cdx-3r-gripper-2-sliding (Autodesk Fusion 360 design; units mm, degrees)
part number: 2026-10-18-13-23-23-866
part number: 2026-10-18-13-23-24-152
part number: 2026-10-18-22-47-35-715
part number: 2026-10-18-22-47-35-720
part number: 2026-10-18-22-47-40-472
part number: 2026-10-18-22-47-42-045
part number: 2026-10-18-22-48-08-572
part number: 2026-10-18-22-48-13-413
part number: 2026-10-19-20-53-59-264
part number: 2026-10-19-20-54-15-154
part number: 2026-10-19-20-58-47-392
part number: 2026-10-19-20-59-14-619
part number: 2026-10-19-21-25-58-125
part number: 2026-10-19-21-26-03-440
part number: 2026-10-19-21-30-46-172
part number: 2026-10-19-21-31-41-430
part number: 2026-10-19-21-31-41-551
part number: 2026-10-19-21-31-56-859
part number: 2026-10-19-21-32-19-291
part number: 2026-10-19-21-32-20-248
part number: 2026-10-19-21-32-33-847
part number: 2026-10-19-21-32-36-535
part number: 2026-10-19-21-32-39-259
part number: 2026-10-19-21-32-56-072
Autodesk Fusion 360 part; units mm, degrees
(part 1 of 5)
ref_plane "WorkPlane1" through (-175, 0, 0) normal (1, 0, 0) x (0, 1, 0) in component "Gripper rail base (printed)"
sketch "spine" plane through (-175, 0, 0) normal (1, 0, 0) x (0, 0, -1) in component "Gripper rail base (printed)"
  line L0 (12, 15) -> (12, 20)
  line L1 (12, 20) -> (-12, 20)
  line L2 (-12, 20) -> (-12, 15)
  line L3 (-12, 15) -> (-12, 15)
  line L4 (-12, 15) -> (-12, 6)
  line L5 (-12, 6) -> (12, 6)
  line L6 (12, 6) -> (12, 15)
  line L7 (12, 15) -> (12, 15)
extrude "spine (1)" add sketch "spine" along normal blind 175.31 makes body 1 in component "Gripper rail base (printed)"
ref_plane "WorkPlane2" through (-130, 0, 0) normal (1, 0, 0) x (0, 1, 0) in component "Gripper rail base (printed)"
sketch "pipe clip" plane through (-130, 0, 0) normal (1, 0, 0) x (0, 0, -1) in component "Gripper rail base (printed)"
  circle A0 centre (0, 0) radius 14.5
  circle A1 centre (0, 0) radius 10.95
extrude "pipe clip (1)" add sketch "pipe clip" along normal blind 12 separate body makes body 2 in component "Gripper rail base (printed)"
ref_plane "WorkPlane3" through (-50, 0, 0) normal (1, 0, 0) x (0, 1, 0) in component "Gripper rail base (printed)"
sketch "pipe clip (1)" plane through (-50, 0, 0) normal (1, 0, 0) x (0, 0, -1) in component "Gripper rail base (printed)"
  circle A0 centre (0, 0) radius 14.5
  circle A1 centre (0, 0) radius 10.95
extrude "pipe clip (2)" add sketch "pipe clip (1)" along normal blind 12 separate body makes body 3 in component "Gripper rail base (printed)"
ref_plane "WorkPlane4" through (0, 0, -12) normal (0, 0, 1) x (1, 0, 0) in component "Gripper rail base (printed)"
sketch "front tab" plane through (0, 0, -12) normal (0, 0, 1) x (1, 0, 0) in component "Gripper rail base (printed)"
  line L0 (0.3, 6) -> (8.3, 6)
  line L1 (8.3, 6) -> (8.3, 20)
  line L2 (8.3, 20) -> (0.3, 20)
  line L3 (0.3, 20) -> (0.3, 6)
extrude "front tab (1)" add sketch "front tab" along normal blind 24 separate body makes body 4 in component "Gripper rail base (printed)"
ref_plane "WorkPlane5" through (0, 16.5, 0) normal (0, 1, 0) x (0, 0, 1) in component "Gripper rail base (printed)"
sketch "rack" plane through (0, 16.5, 0) normal (0, 1, 0) x (1, 0, 0) in component "Gripper rail base (printed)"
  line L0 (-150, -11.5) -> (-150, -12)
  line L1 (-150, -12) -> (-149.6696, -12)
  line L2 (-149.6696, -12) -> (-148.8506, -14.25)
  line L3 (-148.8506, -14.25) -> (-148.0078, -14.25)
  line L4 (-148.0078, -14.25) -> (-147.1888, -12)
  line L5 (-147.1888, -12) -> (-146.528, -12)
  line L6 (-146.528, -12) -> (-145.709, -14.25)
  line L7 (-145.709, -14.25) -> (-144.8662, -14.25)
  line L8 (-144.8662, -14.25) -> (-144.0473, -12)
  line L9 (-144.0473, -12) -> (-143.3864, -12)
  line L10 (-143.3864, -12) -> (-142.5674, -14.25)
  line L11 (-142.5674, -14.25) -> (-141.7246, -14.25)
  line L12 (-141.7246, -14.25) -> (-140.9057, -12)
  line L13 (-140.9057, -12) -> (-140.2448, -12)
  line L14 (-140.2448, -12) -> (-139.4259, -14.25)
  line L15 (-139.4259, -14.25) -> (-138.583, -14.25)
  line L16 (-138.583, -14.25) -> (-137.7641, -12)
  line L17 (-137.7641, -12) -> (-137.1032, -12)
  line L18 (-137.1032, -12) -> (-136.2843, -14.25)
  line L19 (-136.2843, -14.25) -> (-135.4414, -14.25)
  line L20 (-135.4414, -14.25) -> (-134.6225, -12)
  line L21 (-134.6225, -12) -> (-133.9616, -12)
  line L22 (-133.9616, -12) -> (-133.1427, -14.25)
  line L23 (-133.1427, -14.25) -> (-132.2998, -14.25)
  line L24 (-132.2998, -14.25) -> (-131.4809, -12)
  line L25 (-131.4809, -12) -> (-130.82, -12)
  line L26 (-130.82, -12) -> (-130.0011, -14.25)
  line L27 (-130.0011, -14.25) -> (-129.1582, -14.25)
  line L28 (-129.1582, -14.25) -> (-128.3393, -12)
  line L29 (-128.3393, -12) -> (-127.6784, -12)
  line L30 (-127.6784, -12) -> (-126.8595, -14.25)
  line L31 (-126.8595, -14.25) -> (-126.0166, -14.25)
  line L32 (-126.0166, -14.25) -> (-125.1977, -12)
  line L33 (-125.1977, -12) -> (-124.5368, -12)
  line L34 (-124.5368, -12) -> (-123.7179, -14.25)
  line L35 (-123.7179, -14.25) -> (-122.875, -14.25)
  line L36 (-122.875, -14.25) -> (-122.0561, -12)
  line L37 (-122.0561, -12) -> (-121.3952, -12)
  line L38 (-121.3952, -12) -> (-120.5763, -14.25)
  line L39 (-120.5763, -14.25) -> (-119.7334, -14.25)
  line L40 (-119.7334, -14.25) -> (-118.9145, -12)
  line L41 (-118.9145, -12) -> (-118.2536, -12)
  line L42 (-118.2536, -12) -> (-117.4347, -14.25)
  line L43 (-117.4347, -14.25) -> (-116.5918, -14.25)
  line L44 (-116.5918, -14.25) -> (-115.7729, -12)
  line L45 (-115.7729, -12) -> (-115.112, -12)
  line L46 (-115.112, -12) -> (-114.2931, -14.25)
  line L47 (-114.2931, -14.25) -> (-113.4503, -14.25)
  line L48 (-113.4503, -14.25) -> (-112.6313, -12)
  line L49 (-112.6313, -12) -> (-111.9705, -12)
  line L50 (-111.9705, -12) -> (-111.1515, -14.25)
  line L51 (-111.1515, -14.25) -> (-110.3087, -14.25)
  line L52 (-110.3087, -14.25) -> (-109.4897, -12)
  line L53 (-109.4897, -12) -> (-108.8289, -12)
  line L54 (-108.8289, -12) -> (-108.0099, -14.25)
  line L55 (-108.0099, -14.25) -> (-107.1671, -14.25)
  line L56 (-107.1671, -14.25) -> (-106.3481, -12)
  line L57 (-106.3481, -12) -> (-105.6873, -12)
  line L58 (-105.6873, -12) -> (-104.8683, -14.25)
  line L59 (-104.8683, -14.25) -> (-104.0255, -14.25)
  line L60 (-104.0255, -14.25) -> (-103.2065, -12)
  line L61 (-103.2065, -12) -> (-102.5457, -12)
  line L62 (-102.5457, -12) -> (-101.7267, -14.25)
  line L63 (-101.7267, -14.25) -> (-100.8839, -14.25)
  line L64 (-100.8839, -14.25) -> (-100.065, -12)
  line L65 (-100.065, -12) -> (-99.4041, -12)
  line L66 (-99.4041, -12) -> (-98.5851, -14.25)
  line L67 (-98.5851, -14.25) -> (-97.7423, -14.25)
  line L68 (-97.7423, -14.25) -> (-96.9234, -12)
  line L69 (-96.9234, -12) -> (-96.2625, -12)
  line L70 (-96.2625, -12) -> (-95.4436, -14.25)
  line L71 (-95.4436, -14.25) -> (-94.6007, -14.25)
  line L72 (-94.6007, -14.25) -> (-93.7818, -12)
  line L73 (-93.7818, -12) -> (-93.1209, -12)
  line L74 (-93.1209, -12) -> (-92.302, -14.25)
  line L75 (-92.302, -14.25) -> (-91.4591, -14.25)
  line L76 (-91.4591, -14.25) -> (-90.6402, -12)
  line L77 (-90.6402, -12) -> (-89.9793, -12)
  line L78 (-89.9793, -12) -> (-89.1604, -14.25)
  line L79 (-89.1604, -14.25) -> (-88.3175, -14.25)
  line L80 (-88.3175, -14.25) -> (-87.4986, -12)
  line L81 (-87.4986, -12) -> (-86.8377, -12)
  line L82 (-86.8377, -12) -> (-86.0188, -14.25)
  line L83 (-86.0188, -14.25) -> (-85.1759, -14.25)
  line L84 (-85.1759, -14.25) -> (-84.357, -12)
  line L85 (-84.357, -12) -> (-83.6961, -12)
  line L86 (-83.6961, -12) -> (-82.8772, -14.25)
  line L87 (-82.8772, -14.25) -> (-82.0343, -14.25)
  line L88 (-82.0343, -14.25) -> (-81.2154, -12)
  line L89 (-81.2154, -12) -> (-80.5545, -12)
  line L90 (-80.5545, -12) -> (-79.7356, -14.25)
  line L91 (-79.7356, -14.25) -> (-78.8927, -14.25)
  line L92 (-78.8927, -14.25) -> (-78.0738, -12)
  line L93 (-78.0738, -12) -> (-77.4129, -12)
  line L94 (-77.4129, -12) -> (-76.594, -14.25)
  line L95 (-76.594, -14.25) -> (-75.7511, -14.25)
  line L96 (-75.7511, -14.25) -> (-74.9322, -12)
  line L97 (-74.9322, -12) -> (-74.2713, -12)
  line L98 (-74.2713, -12) -> (-73.4524, -14.25)
  line L99 (-73.4524, -14.25) -> (-72.6096, -14.25)
  line L100 (-72.6096, -14.25) -> (-71.7906, -12)
  line L101 (-71.7906, -12) -> (-71.1297, -12)
  line L102 (-71.1297, -12) -> (-70.3108, -14.25)
  line L103 (-70.3108, -14.25) -> (-69.468, -14.25)
  line L104 (-69.468, -14.25) -> (-68.649, -12)
  line L105 (-68.649, -12) -> (-67.9882, -12)
  line L106 (-67.9882, -12) -> (-67.1692, -14.25)
  line L107 (-67.1692, -14.25) -> (-66.3264, -14.25)
  line L108 (-66.3264, -14.25) -> (-65.5074, -12)
  line L109 (-65.5074, -12) -> (-64.8466, -12)
  line L110 (-64.8466, -12) -> (-64.0276, -14.25)
  line L111 (-64.0276, -14.25) -> (-63.1848, -14.25)
  line L112 (-63.1848, -14.25) -> (-62.3658, -12)
  line L113 (-62.3658, -12) -> (-61.705, -12)
  line L114 (-61.705, -12) -> (-60.886, -14.25)
  line L115 (-60.886, -14.25) -> (-60.0432, -14.25)
  line L116 (-60.0432, -14.25) -> (-59.2242, -12)
  line L117 (-59.2242, -12) -> (-58.5634, -12)
  line L118 (-58.5634, -12) -> (-57.7444, -14.25)
  line L119 (-57.7444, -14.25) -> (-56.9016, -14.25)
  line L120 (-56.9016, -14.25) -> (-56.0827, -12)
  line L121 (-56.0827, -12) -> (-55.4218, -12)
  line L122 (-55.4218, -12) -> (-54.6029, -14.25)
  line L123 (-54.6029, -14.25) -> (-53.76, -14.25)
  line L124 (-53.76, -14.25) -> (-52.9411, -12)
  line L125 (-52.9411, -12) -> (-52.2802, -12)
  line L126 (-52.2802, -12) -> (-51.4613, -14.25)
  line L127 (-51.4613, -14.25) -> (-50.6184, -14.25)
  line L128 (-50.6184, -14.25) -> (-49.7995, -12)
  line L129 (-49.7995, -12) -> (-49.1386, -12)
  line L130 (-49.1386, -12) -> (-48.3197, -14.25)
  line L131 (-48.3197, -14.25) -> (-47.4768, -14.25)
  line L132 (-47.4768, -14.25) -> (-46.6579, -12)
  line L133 (-46.6579, -12) -> (-45.997, -12)
  line L134 (-45.997, -12) -> (-45.1781, -14.25)
  line L135 (-45.1781, -14.25) -> (-44.3352, -14.25)
  line L136 (-44.3352, -14.25) -> (-43.5163, -12)
  line L137 (-43.5163, -12) -> (-42.8554, -12)
  line L138 (-42.8554, -12) -> (-42.0365, -14.25)
  line L139 (-42.0365, -14.25) -> (-41.1936, -14.25)
  line L140 (-41.1936, -14.25) -> (-40.3747, -12)
  line L141 (-40.3747, -12) -> (-39.7138, -12)
  line L142 (-39.7138, -12) -> (-38.8949, -14.25)
  line L143 (-38.8949, -14.25) -> (-38.052, -14.25)
  line L144 (-38.052, -14.25) -> (-37.2331, -12)
  line L145 (-37.2331, -12) -> (-36.5722, -12)
  line L146 (-36.5722, -12) -> (-35.7533, -14.25)
  line L147 (-35.7533, -14.25) -> (-34.9104, -14.25)
  line L148 (-34.9104, -14.25) -> (-34.0915, -12)
  line L149 (-34.0915, -12) -> (-33.4306, -12)
  line L150 (-33.4306, -12) -> (-32.6117, -14.25)
  line L151 (-32.6117, -14.25) -> (-31.7688, -14.25)
  line L152 (-31.7688, -14.25) -> (-30.9499, -12)
  line L153 (-30.9499, -12) -> (-30.289, -12)
  line L154 (-30.289, -12) -> (-29.4701, -14.25)
  line L155 (-29.4701, -14.25) -> (-28.6273, -14.25)
  line L156 (-28.6273, -14.25) -> (-27.8083, -12)
  line L157 (-27.8083, -12) -> (-27.1475, -12)
  line L158 (-27.1475, -12) -> (-26.3285, -14.25)
  line L159 (-26.3285, -14.25) -> (-25.4857, -14.25)
  line L160 (-25.4857, -14.25) -> (-24.6667, -12)
  line L161 (-24.6667, -12) -> (-24.0059, -12)
  line L162 (-24.0059, -12) -> (-23.1869, -14.25)
  line L163 (-23.1869, -14.25) -> (-22.3441, -14.25)
  line L164 (-22.3441, -14.25) -> (-21.5251, -12)
  line L165 (-21.5251, -12) -> (-20.8643, -12)
  line L166 (-20.8643, -12) -> (-20.0453, -14.25)
  line L167 (-20.0453, -14.25) -> (-19.2025, -14.25)
  line L168 (-19.2025, -14.25) -> (-18.3835, -12)
  line L169 (-18.3835, -12) -> (-17.7227, -12)
  line L170 (-17.7227, -12) -> (-16.9037, -14.25)
  line L171 (-16.9037, -14.25) -> (-16.0609, -14.25)
  line L172 (-16.0609, -14.25) -> (-15.242, -12)
  line L173 (-15.242, -12) -> (-14.5811, -12)
  line L174 (-14.5811, -12) -> (-13.7621, -14.25)
  line L175 (-13.7621, -14.25) -> (-12.9193, -14.25)
  line L176 (-12.9193, -14.25) -> (-12.1004, -12)
  line L177 (-12.1004, -12) -> (-11.4395, -12)
  line L178 (-11.4395, -12) -> (-10.6206, -14.25)
  line L179 (-10.6206, -14.25) -> (-9.7777, -14.25)
  line L180 (-9.7777, -14.25) -> (-8.9588, -12)
  line L181 (-8.9588, -12) -> (-8.2979, -12)
  line L182 (-8.2979, -12) -> (-7.479, -14.25)
  line L183 (-7.479, -14.25) -> (-6.6361, -14.25)
  line L184 (-6.6361, -14.25) -> (-5.8172, -12)
  line L185 (-5.8172, -12) -> (-5.1563, -12)
  line L186 (-5.1563, -12) -> (-4.3374, -14.25)
  line L187 (-4.3374, -14.25) -> (-3.4945, -14.25)
  line L188 (-3.4945, -14.25) -> (-2.6756, -12)
  line L189 (-2.6756, -12) -> (0, -12)
  line L190 (0, -12) -> (0, -11.5)
  line L191 (0, -11.5) -> (-150, -11.5)
extrude "rack (1)" add sketch "rack" along normal blind 3.49 separate body makes body 5 in component "Gripper rail base (printed)"
sketch "rack (1)" plane through (0, 16.5, 0) normal (0, 1, 0) x (1, 0, 0) in component "Gripper rail base (printed)"
  line L0 (-150, 11.5) -> (-150, 12)
  line L1 (-150, 12) -> (-149.6696, 12)
  line L2 (-149.6696, 12) -> (-148.8506, 14.25)
  line L3 (-148.8506, 14.25) -> (-148.0078, 14.25)
  line L4 (-148.0078, 14.25) -> (-147.1888, 12)
  line L5 (-147.1888, 12) -> (-146.528, 12)
  line L6 (-146.528, 12) -> (-145.709, 14.25)
  line L7 (-145.709, 14.25) -> (-144.8662, 14.25)
  line L8 (-144.8662, 14.25) -> (-144.0473, 12)
  line L9 (-144.0473, 12) -> (-143.3864, 12)
  line L10 (-143.3864, 12) -> (-142.5674, 14.25)
  line L11 (-142.5674, 14.25) -> (-141.7246, 14.25)
  line L12 (-141.7246, 14.25) -> (-140.9057, 12)
  line L13 (-140.9057, 12) -> (-140.2448, 12)
  line L14 (-140.2448, 12) -> (-139.4259, 14.25)
  line L15 (-139.4259, 14.25) -> (-138.583, 14.25)
  line L16 (-138.583, 14.25) -> (-137.7641, 12)
  line L17 (-137.7641, 12) -> (-137.1032, 12)
  line L18 (-137.1032, 12) -> (-136.2843, 14.25)
  line L19 (-136.2843, 14.25) -> (-135.4414, 14.25)
  line L20 (-135.4414, 14.25) -> (-134.6225, 12)
  line L21 (-134.6225, 12) -> (-133.9616, 12)
  line L22 (-133.9616, 12) -> (-133.1427, 14.25)
  line L23 (-133.1427, 14.25) -> (-132.2998, 14.25)
  line L24 (-132.2998, 14.25) -> (-131.4809, 12)
  line L25 (-131.4809, 12) -> (-130.82, 12)
  line L26 (-130.82, 12) -> (-130.0011, 14.25)
  line L27 (-130.0011, 14.25) -> (-129.1582, 14.25)
  line L28 (-129.1582, 14.25) -> (-128.3393, 12)
  line L29 (-128.3393, 12) -> (-127.6784, 12)
  line L30 (-127.6784, 12) -> (-126.8595, 14.25)
  line L31 (-126.8595, 14.25) -> (-126.0166, 14.25)
  line L32 (-126.0166, 14.25) -> (-125.1977, 12)
  line L33 (-125.1977, 12) -> (-124.5368, 12)
  line L34 (-124.5368, 12) -> (-123.7179, 14.25)
  line L35 (-123.7179, 14.25) -> (-122.875, 14.25)
  line L36 (-122.875, 14.25) -> (-122.0561, 12)
  line L37 (-122.0561, 12) -> (-121.3952, 12)
  line L38 (-121.3952, 12) -> (-120.5763, 14.25)
  line L39 (-120.5763, 14.25) -> (-119.7334, 14.25)
  line L40 (-119.7334, 14.25) -> (-118.9145, 12)
  line L41 (-118.9145, 12) -> (-118.2536, 12)
  line L42 (-118.2536, 12) -> (-117.4347, 14.25)
  line L43 (-117.4347, 14.25) -> (-116.5918, 14.25)
  line L44 (-116.5918, 14.25) -> (-115.7729, 12)
  line L45 (-115.7729, 12) -> (-115.112, 12)
  line L46 (-115.112, 12) -> (-114.2931, 14.25)
  line L47 (-114.2931, 14.25) -> (-113.4503, 14.25)
  line L48 (-113.4503, 14.25) -> (-112.6313, 12)
  line L49 (-112.6313, 12) -> (-111.9705, 12)
  line L50 (-111.9705, 12) -> (-111.1515, 14.25)
  line L51 (-111.1515, 14.25) -> (-110.3087, 14.25)
  line L52 (-110.3087, 14.25) -> (-109.4897, 12)
  line L53 (-109.4897, 12) -> (-108.8289, 12)
  line L54 (-108.8289, 12) -> (-108.0099, 14.25)
  line L55 (-108.0099, 14.25) -> (-107.1671, 14.25)
  line L56 (-107.1671, 14.25) -> (-106.3481, 12)
  line L57 (-106.3481, 12) -> (-105.6873, 12)
  line L58 (-105.6873, 12) -> (-104.8683, 14.25)
  line L59 (-104.8683, 14.25) -> (-104.0255, 14.25)
  line L60 (-104.0255, 14.25) -> (-103.2065, 12)
  line L61 (-103.2065, 12) -> (-102.5457, 12)
  line L62 (-102.5457, 12) -> (-101.7267, 14.25)
  line L63 (-101.7267, 14.25) -> (-100.8839, 14.25)
  line L64 (-100.8839, 14.25) -> (-100.065, 12)
  line L65 (-100.065, 12) -> (-99.4041, 12)
  line L66 (-99.4041, 12) -> (-98.5851, 14.25)
  line L67 (-98.5851, 14.25) -> (-97.7423, 14.25)
  line L68 (-97.7423, 14.25) -> (-96.9234, 12)
  line L69 (-96.9234, 12) -> (-96.2625, 12)
  line L70 (-96.2625, 12) -> (-95.4436, 14.25)
  line L71 (-95.4436, 14.25) -> (-94.6007, 14.25)
  line L72 (-94.6007, 14.25) -> (-93.7818, 12)
  line L73 (-93.7818, 12) -> (-93.1209, 12)
  line L74 (-93.1209, 12) -> (-92.302, 14.25)
  line L75 (-92.302, 14.25) -> (-91.4591, 14.25)
  line L76 (-91.4591, 14.25) -> (-90.6402, 12)
  line L77 (-90.6402, 12) -> (-89.9793, 12)
  line L78 (-89.9793, 12) -> (-89.1604, 14.25)
  line L79 (-89.1604, 14.25) -> (-88.3175, 14.25)
  line L80 (-88.3175, 14.25) -> (-87.4986, 12)
  line L81 (-87.4986, 12) -> (-86.8377, 12)
  line L82 (-86.8377, 12) -> (-86.0188, 14.25)
  line L83 (-86.0188, 14.25) -> (-85.1759, 14.25)
  line L84 (-85.1759, 14.25) -> (-84.357, 12)
  line L85 (-84.357, 12) -> (-83.6961, 12)
  line L86 (-83.6961, 12) -> (-82.8772, 14.25)
  line L87 (-82.8772, 14.25) -> (-82.0343, 14.25)
  line L88 (-82.0343, 14.25) -> (-81.2154, 12)
  line L89 (-81.2154, 12) -> (-80.5545, 12)
  line L90 (-80.5545, 12) -> (-79.7356, 14.25)
  line L91 (-79.7356, 14.25) -> (-78.8927, 14.25)
  line L92 (-78.8927, 14.25) -> (-78.0738, 12)
  line L93 (-78.0738, 12) -> (-77.4129, 12)
  line L94 (-77.4129, 12) -> (-76.594, 14.25)
  line L95 (-76.594, 14.25) -> (-75.7511, 14.25)
  line L96 (-75.7511, 14.25) -> (-74.9322, 12)
  line L97 (-74.9322, 12) -> (-74.2713, 12)
  line L98 (-74.2713, 12) -> (-73.4524, 14.25)
  line L99 (-73.4524, 14.25) -> (-72.6096, 14.25)
  line L100 (-72.6096, 14.25) -> (-71.7906, 12)
  line L101 (-71.7906, 12) -> (-71.1297, 12)
  line L102 (-71.1297, 12) -> (-70.3108, 14.25)
  line L103 (-70.3108, 14.25) -> (-69.468, 14.25)
  line L104 (-69.468, 14.25) -> (-68.649, 12)
  line L105 (-68.649, 12) -> (-67.9882, 12)
  line L106 (-67.9882, 12) -> (-67.1692, 14.25)
  line L107 (-67.1692, 14.25) -> (-66.3264, 14.25)
  line L108 (-66.3264, 14.25) -> (-65.5074, 12)
  line L109 (-65.5074, 12) -> (-64.8466, 12)
  line L110 (-64.8466, 12) -> (-64.0276, 14.25)
  line L111 (-64.0276, 14.25) -> (-63.1848, 14.25)
  line L112 (-63.1848, 14.25) -> (-62.3658, 12)
  line L113 (-62.3658, 12) -> (-61.705, 12)
  line L114 (-61.705, 12) -> (-60.886, 14.25)
  line L115 (-60.886, 14.25) -> (-60.0432, 14.25)
  line L116 (-60.0432, 14.25) -> (-59.2242, 12)
  line L117 (-59.2242, 12) -> (-58.5634, 12)
  line L118 (-58.5634, 12) -> (-57.7444, 14.25)
  line L119 (-57.7444, 14.25) -> (-56.9016, 14.25)
  line L120 (-56.9016, 14.25) -> (-56.0827, 12)
  line L121 (-56.0827, 12) -> (-55.4218, 12)
  line L122 (-55.4218, 12) -> (-54.6029, 14.25)
  line L123 (-54.6029, 14.25) -> (-53.76, 14.25)
  line L124 (-53.76, 14.25) -> (-52.9411, 12)
  line L125 (-52.9411, 12) -> (-52.2802, 12)
  line L126 (-52.2802, 12) -> (-51.4613, 14.25)
  line L127 (-51.4613, 14.25) -> (-50.6184, 14.25)
  line L128 (-50.6184, 14.25) -> (-49.7995, 12)
  line L129 (-49.7995, 12) -> (-49.1386, 12)
  line L130 (-49.1386, 12) -> (-48.3197, 14.25)
  line L131 (-48.3197, 14.25) -> (-47.4768, 14.25)
  line L132 (-47.4768, 14.25) -> (-46.6579, 12)
  line L133 (-46.6579, 12) -> (-45.997, 12)
  line L134 (-45.997, 12) -> (-45.1781, 14.25)
  line L135 (-45.1781, 14.25) -> (-44.3352, 14.25)
  line L136 (-44.3352, 14.25) -> (-43.5163, 12)
  line L137 (-43.5163, 12) -> (-42.8554, 12)
  line L138 (-42.8554, 12) -> (-42.0365, 14.25)
  line L139 (-42.0365, 14.25) -> (-41.1936, 14.25)
  line L140 (-41.1936, 14.25) -> (-40.3747, 12)
  line L141 (-40.3747, 12) -> (-39.7138, 12)
  line L142 (-39.7138, 12) -> (-38.8949, 14.25)
  line L143 (-38.8949, 14.25) -> (-38.052, 14.25)
  line L144 (-38.052, 14.25) -> (-37.2331, 12)
  line L145 (-37.2331, 12) -> (-36.5722, 12)
  line L146 (-36.5722, 12) -> (-35.7533, 14.25)
  line L147 (-35.7533, 14.25) -> (-34.9104, 14.25)
  line L148 (-34.9104, 14.25) -> (-34.0915, 12)
  line L149 (-34.0915, 12) -> (-33.4306, 12)
  line L150 (-33.4306, 12) -> (-32.6117, 14.25)
  line L151 (-32.6117, 14.25) -> (-31.7688, 14.25)
  line L152 (-31.7688, 14.25) -> (-30.9499, 12)
  line L153 (-30.9499, 12) -> (-30.289, 12)
  line L154 (-30.289, 12) -> (-29.4701, 14.25)
  line L155 (-29.4701, 14.25) -> (-28.6273, 14.25)
  line L156 (-28.6273, 14.25) -> (-27.8083, 12)
  line L157 (-27.8083, 12) -> (-27.1475, 12)
  line L158 (-27.1475, 12) -> (-26.3285, 14.25)
  line L159 (-26.3285, 14.25) -> (-25.4857, 14.25)
  line L160 (-25.4857, 14.25) -> (-24.6667, 12)
  line L161 (-24.6667, 12) -> (-24.0059, 12)
  line L162 (-24.0059, 12) -> (-23.1869, 14.25)
  line L163 (-23.1869, 14.25) -> (-22.3441, 14.25)
  line L164 (-22.3441, 14.25) -> (-21.5251, 12)
  line L165 (-21.5251, 12) -> (-20.8643, 12)
  line L166 (-20.8643, 12) -> (-20.0453, 14.25)
  line L167 (-20.0453, 14.25) -> (-19.2025, 14.25)
  line L168 (-19.2025, 14.25) -> (-18.3835, 12)
  line L169 (-18.3835, 12) -> (-17.7227, 12)
  line L170 (-17.7227, 12) -> (-16.9037, 14.25)
  line L171 (-16.9037, 14.25) -> (-16.0609, 14.25)
  line L172 (-16.0609, 14.25) -> (-15.242, 12)
  line L173 (-15.242, 12) -> (-14.5811, 12)
  line L174 (-14.5811, 12) -> (-13.7621, 14.25)
  line L175 (-13.7621, 14.25) -> (-12.9193, 14.25)
  line L176 (-12.9193, 14.25) -> (-12.1004, 12)
  line L177 (-12.1004, 12) -> (-11.4395, 12)
  line L178 (-11.4395, 12) -> (-10.6206, 14.25)
  line L179 (-10.6206, 14.25) -> (-9.7777, 14.25)
  line L180 (-9.7777, 14.25) -> (-8.9588, 12)
  line L181 (-8.9588, 12) -> (-8.2979, 12)
  line L182 (-8.2979, 12) -> (-7.479, 14.25)
  line L183 (-7.479, 14.25) -> (-6.6361, 14.25)
  line L184 (-6.6361, 14.25) -> (-5.8172, 12)
  line L185 (-5.8172, 12) -> (-5.1563, 12)
  line L186 (-5.1563, 12) -> (-4.3374, 14.25)
  line L187 (-4.3374, 14.25) -> (-3.4945, 14.25)
  line L188 (-3.4945, 14.25) -> (-2.6756, 12)
  line L189 (-2.6756, 12) -> (0, 12)
  line L190 (0, 12) -> (0, 11.5)
  line L191 (0, 11.5) -> (-150, 11.5)
extrude "rack (2)" add sketch "rack (1)" along normal blind 3.49 separate body makes body 6 in component "Gripper rail base (printed)"
ref_plane "WorkPlane6" through (0, 0, 11.99) normal (0, 0, 1) x (1, 0, 0) in component "Gripper rail base (printed)"
sketch "spool lug" plane through (0, 0, 11.99) normal (0, 0, 1) x (1, 0, 0) in component "Gripper rail base (printed)"
  line L0 (-175, 15) -> (-154, 15)
  line L1 (-154, 15) -> (-154, 20)
  line L2 (-154, 20) -> (-175, 20)
  line L3 (-175, 20) -> (-175, 15)
extrude "spool lug (1)" add sketch "spool lug" along normal blind 20.01 separate body makes body 7 in component "Gripper rail base (printed)"
ref_plane "WorkPlane7" through (0, 20, 0) normal (0, 1, 0) x (0, 0, 1) in component "Gripper rail base (printed)"
sketch "spool boss" plane through (0, 20, 0) normal (0, 1, 0) x (1, 0, 0) in component "Gripper rail base (printed)"
  circle A0 centre (-164, -22) radius 4
extrude "spool boss (1)" add sketch "spool boss" along normal blind 8.5 separate body makes body 8 in component "Gripper rail base (printed)"
combine "Combine1" operation add target body 1 tool bodies 2 in component "Gripper rail base (printed)"
combine "Combine2" operation add target body 1 tool bodies 3 in component "Gripper rail base (printed)"
combine "Combine3" operation add target body 1 tool bodies 4 in component "Gripper rail base (printed)"
combine "Combine4" operation add target body 1 tool bodies 5 in component "Gripper rail base (printed)"
combine "Combine5" operation add target body 1 tool bodies 6 in component "Gripper rail base (printed)"
combine "Combine6" operation add target body 1 tool bodies 7 in component "Gripper rail base (printed)"
combine "Combine7" operation add target body 1 tool bodies 8 in component "Gripper rail base (printed)"
ref_plane "WorkPlane8" through (-176, 0, 0) normal (1, 0, 0) x (0, 1, 0) in component "Gripper rail base (printed)"
sketch "pipe bore" plane through (-176, 0, 0) normal (1, 0, 0) x (0, 0, -1) in component "Gripper rail base (printed)"
  circle A0 centre (0, 0) radius 10.95
extrude "pipe bore (1)" cut sketch "pipe bore" along normal blind 177.31 bodies 1 in component "Gripper rail base (printed)"
ref_plane "WorkPlane9" through (-28.5, 0, 0) normal (1, 0, 0) x (0, 1, 0) in component "Gripper rail base (printed)"
sketch "ring clearance" plane through (-28.5, 0, 0) normal (1, 0, 0) x (0, 0, -1) in component "Gripper rail base (printed)"
  line L0 (40, -30) -> (-40, -30)
  line L1 (-40, -30) -> (-40, 16.4)
  line L2 (-40, 16.4) -> (40, 16.4)
  line L3 (40, 16.4) -> (40, -30)
extrude "ring clearance (1)" cut sketch "ring clearance" along normal blind 29 bodies 1 in component "Gripper rail base (printed)"
sketch "ring clearance (1)" plane through (-176, 0, 0) normal (1, 0, 0) x (0, 0, -1) in component "Gripper rail base (printed)"
  line L0 (40, -30) -> (-40, -30)
  line L1 (-40, -30) -> (-40, 16.4)
  line L2 (-40, 16.4) -> (40, 16.4)
  line L3 (40, 16.4) -> (40, -30)
extrude "ring clearance (2)" cut sketch "ring clearance (1)" along normal blind 16.5 bodies 1 in component "Gripper rail base (printed)"
ref_plane "WorkPlane10" through (0, 0, -20) normal (0, 0, 1) x (1, 0, 0) in component "Gripper rail base (printed)"
sketch "clip openings" plane through (0, 0, -20) normal (0, 0, 1) x (1, 0, 0) in component "Gripper rail base (printed)"
  line L0 (-200, -30) -> (20, -30)
  line L1 (20, -30) -> (20, -7.25)
  line L2 (20, -7.25) -> (-200, -7.25)
  line L3 (-200, -7.25) -> (-200, -30)
extrude "clip openings (1)" cut sketch "clip openings" along normal blind 40 bodies 1 in component "Gripper rail base (printed)"
ref_plane "WorkPlane11" through (0, 8, 0) normal (0, 1, 0) x (0, 0, 1) in component "Gripper rail base (printed)"
sketch "pipe screw hole" plane through (0, 8, 0) normal (0, 1, 0) x (1, 0, 0) in component "Gripper rail base (printed)"
  circle A0 centre (-124, 0) radius 1.65
extrude "pipe screw hole (1)" cut sketch "pipe screw hole" along normal blind 13 bodies 1 in component "Gripper rail base (printed)"
ref_plane "WorkPlane12" through (0, 13.5, 0) normal (0, 1, 0) x (0, 0, 1) in component "Gripper rail base (printed)"
sketch "pipe screw counterbore" plane through (0, 13.5, 0) normal (0, 1, 0) x (1, 0, 0) in component "Gripper rail base (printed)"
  circle A0 centre (-124, 0) radius 3.4
extrude "pipe screw counterbore (1)" cut sketch "pipe screw counterbore" along normal blind 7.5 bodies 1 in component "Gripper rail base (printed)"
sketch "pipe screw hole (1)" plane through (0, 8, 0) normal (0, 1, 0) x (1, 0, 0) in component "Gripper rail base (printed)"
  circle A0 centre (-44, 0) radius 1.65
extrude "pipe screw hole (2)" cut sketch "pipe screw hole (1)" along normal blind 13 bodies 1 in component "Gripper rail base (printed)"
sketch "pipe screw counterbore (1)" plane through (0, 13.5, 0) normal (0, 1, 0) x (1, 0, 0) in component "Gripper rail base (printed)"
  circle A0 centre (-44, 0) radius 3.4
extrude "pipe screw counterbore (2)" cut sketch "pipe screw counterbore (1)" along normal blind 7.5 bodies 1 in component "Gripper rail base (printed)"
ref_plane "WorkPlane13" through (-1, 0, 0) normal (1, 0, 0) x (0, 1, 0) in component "Gripper rail base (printed)"
sketch "ring screw hole" plane through (-1, 0, 0) normal (1, 0, 0) x (0, 0, -1) in component "Gripper rail base (printed)"
  circle A0 centre (0, 13.5) radius 1.65
extrude "ring screw hole (1)" cut sketch "ring screw hole" along normal blind 10.3 bodies 1 in component "Gripper rail base (printed)"
ref_plane "WorkPlane14" through (3, 0, 0) normal (1, 0, 0) x (0, 1, 0) in component "Gripper rail base (printed)"
sketch "ring screw counterbore" plane through (3, 0, 0) normal (1, 0, 0) x (0, 0, -1) in component "Gripper rail base (printed)"
  circle A0 centre (0, 13.5) radius 3.4
extrude "ring screw counterbore (1)" cut sketch "ring screw counterbore" along normal blind 6.3 bodies 1 in component "Gripper rail base (printed)"
ref_plane "WorkPlane15" through (2.4, 0, 0) normal (1, 0, 0) x (0, 1, 0) in component "Gripper rail base (printed)"
sketch "insert hole" plane through (2.4, 0, 0) normal (1, 0, 0) x (0, 0, -1) in component "Gripper rail base (printed)"
  circle A0 centre (-5, 9.5) radius 2
extrude "insert hole (1)" cut sketch "insert hole" along normal blind 6.9 bodies 1 in component "Gripper rail base (printed)"
sketch "insert hole (1)" plane through (2.4, 0, 0) normal (1, 0, 0) x (0, 0, -1) in component "Gripper rail base (printed)"
  circle A0 centre (-8, 16.5) radius 2
extrude "insert hole (2)" cut sketch "insert hole (1)" along normal blind 6.9 bodies 1 in component "Gripper rail base (printed)"
ref_plane "WorkPlane16" through (0, 13, 0) normal (0, 1, 0) x (0, 0, 1) in component "Gripper rail base (printed)"
sketch "rail insert hole" plane through (0, 13, 0) normal (0, 1, 0) x (1, 0, 0) in component "Gripper rail base (printed)"
  circle A0 centre (-152.5, 0) radius 2
extrude "rail insert hole (1)" cut sketch "rail insert hole" along normal blind 8 bodies 1 in component "Gripper rail base (printed)"
sketch "rail insert hole (1)" plane through (0, 13, 0) normal (0, 1, 0) x (1, 0, 0) in component "Gripper rail base (printed)"
  circle A0 centre (-102.5, 0) radius 2
extrude "rail insert hole (2)" cut sketch "rail insert hole (1)" along normal blind 8 bodies 1 in component "Gripper rail base (printed)"
sketch "rail insert hole (2)" plane through (0, 13, 0) normal (0, 1, 0) x (1, 0, 0) in component "Gripper rail base (printed)"
  circle A0 centre (-52.5, 0) radius 2
extrude "rail insert hole (3)" cut sketch "rail insert hole (2)" along normal blind 8 bodies 1 in component "Gripper rail base (printed)"
sketch "spool insert hole" plane through (0, 20, 0) normal (0, 1, 0) x (1, 0, 0) in component "Gripper rail base (printed)"
  circle A0 centre (-164, -22) radius 2
extrude "spool insert hole (1)" cut sketch "spool insert hole" along normal blind 9.5 bodies 1 in component "Gripper rail base (printed)"
ref_plane "WorkPlane1" through (0, 0, -6) normal (0, 0, 1) x (1, 0, 0) in component "Gripper rail MGN12 (buy)"
sketch "rail" plane through (0, 0, -6) normal (0, 0, 1) x (1, 0, 0) in component "Gripper rail MGN12 (buy)"
  line L0 (-165, 20) -> (135, 20)
  line L1 (135, 20) -> (135, 28)
  line L2 (135, 28) -> (-165, 28)
  line L3 (-165, 28) -> (-165, 20)
extrude "rail (1)" add sketch "rail" along normal blind 12 separate body makes body 9 in component "Gripper rail MGN12 (buy)"
ref_plane "WorkPlane2" through (0, 24.5, 0) normal (0, 1, 0) x (0, 0, 1) in component "Gripper rail MGN12 (buy)"
sketch "screw counterbore" plane through (0, 24.5, 0) normal (0, 1, 0) x (1, 0, 0) in component "Gripper rail MGN12 (buy)"
  circle A0 centre (-152.5, 0) radius 3
extrude "screw counterbore (1)" cut sketch "screw counterbore" along normal blind 4.5 bodies 9 in component "Gripper rail MGN12 (buy)"
ref_plane "WorkPlane3" through (0, 19, 0) normal (0, 1, 0) x (0, 0, 1) in component "Gripper rail MGN12 (buy)"
sketch "screw hole" plane through (0, 19, 0) normal (0, 1, 0) x (1, 0, 0) in component "Gripper rail MGN12 (buy)"
  circle A0 centre (-152.5, 0) radius 1.75
extrude "screw hole (1)" cut sketch "screw hole" along normal blind 10 bodies 9 in component "Gripper rail MGN12 (buy)"
sketch "screw counterbore (1)" plane through (0, 24.5, 0) normal (0, 1, 0) x (1, 0, 0) in component "Gripper rail MGN12 (buy)"
  circle A0 centre (-102.5, 0) radius 3
extrude "screw counterbore (2)" cut sketch "screw counterbore (1)" along normal blind 4.5 bodies 9 in component "Gripper rail MGN12 (buy)"
sketch "screw hole (1)" plane through (0, 19, 0) normal (0, 1, 0) x (1, 0, 0) in component "Gripper rail MGN12 (buy)"
  circle A0 centre (-102.5, 0) radius 1.75
extrude "screw hole (2)" cut sketch "screw hole (1)" along normal blind 10 bodies 9 in component "Gripper rail MGN12 (buy)"
sketch "screw counterbore (2)" plane through (0, 24.5, 0) normal (0, 1, 0) x (1, 0, 0) in component "Gripper rail MGN12 (buy)"
  circle A0 centre (-52.5, 0) radius 3
extrude "screw counterbore (3)" cut sketch "screw counterbore (2)" along normal blind 4.5 bodies 9 in component "Gripper rail MGN12 (buy)"
sketch "screw hole (2)" plane through (0, 19, 0) normal (0, 1, 0) x (1, 0, 0) in component "Gripper rail MGN12 (buy)"
  circle A0 centre (-52.5, 0) radius 1.75
extrude "screw hole (3)" cut sketch "screw hole (2)" along normal blind 10 bodies 9 in component "Gripper rail MGN12 (buy)"
sketch "screw counterbore (3)" plane through (0, 24.5, 0) normal (0, 1, 0) x (1, 0, 0) in component "Gripper rail MGN12 (buy)"
  circle A0 centre (22.5, 0) radius 3
extrude "screw counterbore (4)" cut sketch "screw counterbore (3)" along normal blind 4.5 bodies 9 in component "Gripper rail MGN12 (buy)"
sketch "screw hole (3)" plane through (0, 19, 0) normal (0, 1, 0) x (1, 0, 0) in component "Gripper rail MGN12 (buy)"
  circle A0 centre (22.5, 0) radius 1.75
extrude "screw hole (4)" cut sketch "screw hole (3)" along normal blind 10 bodies 9 in component "Gripper rail MGN12 (buy)"
sketch "screw counterbore (4)" plane through (0, 24.5, 0) normal (0, 1, 0) x (1, 0, 0) in component "Gripper rail MGN12 (buy)"
  circle A0 centre (72.5, 0) radius 3
extrude "screw counterbore (5)" cut sketch "screw counterbore (4)" along normal blind 4.5 bodies 9 in component "Gripper rail MGN12 (buy)"
sketch "screw hole (4)" plane through (0, 19, 0) normal (0, 1, 0) x (1, 0, 0) in component "Gripper rail MGN12 (buy)"
  circle A0 centre (72.5, 0) radius 1.75
extrude "screw hole (5)" cut sketch "screw hole (4)" along normal blind 10 bodies 9 in component "Gripper rail MGN12 (buy)"
sketch "screw counterbore (5)" plane through (0, 24.5, 0) normal (0, 1, 0) x (1, 0, 0) in component "Gripper rail MGN12 (buy)"
  circle A0 centre (122.5, 0) radius 3
extrude "screw counterbore (6)" cut sketch "screw counterbore (5)" along normal blind 4.5 bodies 9 in component "Gripper rail MGN12 (buy)"
sketch "screw hole (5)" plane through (0, 19, 0) normal (0, 1, 0) x (1, 0, 0) in component "Gripper rail MGN12 (buy)"
  circle A0 centre (122.5, 0) radius 1.75
extrude "screw hole (6)" cut sketch "screw hole (5)" along normal blind 10 bodies 9 in component "Gripper rail MGN12 (buy)"
ref_plane "WorkPlane1" through (0, 0, -13.5) normal (0, 0, 1) x (1, 0, 0) in component "Gripper carriage MGN12H (buy)"
sketch "carriage" plane through (0, 0, -13.5) normal (0, 0, 1) x (1, 0, 0) in component "Gripper carriage MGN12H (buy)"
  line L0 (-161.7, 24) -> (-116.3, 24)
  line L1 (-116.3, 24) -> (-116.3, 33)
  line L2 (-116.3, 33) -> (-161.7, 33)
  line L3 (-161.7, 33) -> (-161.7, 24)
extrude "carriage (1)" add sketch "carriage" along normal blind 27 separate body makes body 10 in component "Gripper carriage MGN12H (buy)"
ref_plane "WorkPlane2" through (-162.7, 0, 0) normal (1, 0, 0) x (0, 1, 0) in component "Gripper carriage MGN12H (buy)"
sketch "rail slot" plane through (-162.7, 0, 0) normal (1, 0, 0) x (0, 0, -1) in component "Gripper carriage MGN12H (buy)"
  line L0 (6.2, 23) -> (-6.2, 23)
  line L1 (-6.2, 23) -> (-6.2, 28.2)
  line L2 (-6.2, 28.2) -> (6.2, 28.2)
  line L3 (6.2, 28.2) -> (6.2, 23)
extrude "rail slot (1)" cut sketch "rail slot" along normal blind 47.4 bodies 10 in component "Gripper carriage MGN12H (buy)"
ref_plane "WorkPlane3" through (0, 27, 0) normal (0, 1, 0) x (0, 0, 1) in component "Gripper carriage MGN12H (buy)"
sketch "M3 tap hole" plane through (0, 27, 0) normal (0, 1, 0) x (1, 0, 0) in component "Gripper carriage MGN12H (buy)"
  circle A0 centre (-149, 10) radius 1.25
extrude "M3 tap hole (1)" cut sketch "M3 tap hole" along normal blind 7 bodies 10 in component "Gripper carriage MGN12H (buy)"
sketch "M3 tap hole (1)" plane through (0, 27, 0) normal (0, 1, 0) x (1, 0, 0) in component "Gripper carriage MGN12H (buy)"
  circle A0 centre (-149, -10) radius 1.25
extrude "M3 tap hole (2)" cut sketch "M3 tap hole (1)" along normal blind 7 bodies 10 in component "Gripper carriage MGN12H (buy)"
sketch "M3 tap hole (2)" plane through (0, 27, 0) normal (0, 1, 0) x (1, 0, 0) in component "Gripper carriage MGN12H (buy)"
  circle A0 centre (-129, 10) radius 1.25
extrude "M3 tap hole (3)" cut sketch "M3 tap hole (2)" along normal blind 7 bodies 10 in component "Gripper carriage MGN12H (buy)"
sketch "M3 tap hole (3)" plane through (0, 27, 0) normal (0, 1, 0) x (1, 0, 0) in component "Gripper carriage MGN12H (buy)"
  circle A0 centre (-129, -10) radius 1.25
extrude "M3 tap hole (4)" cut sketch "M3 tap hole (3)" along normal blind 7 bodies 10 in component "Gripper carriage MGN12H (buy)"
ref_plane "WorkPlane1" through (0, 39.2, 0) normal (0, 1, 0) x (0, 0, 1) in component "Gripper finger R (TPU)"
sketch "finger" plane through (0, 39.2, 0) normal (0, 1, 0) x (1, 0, 0) in component "Gripper finger R (TPU)"
  line L0 (-120, -1) -> (14, -1)
  line L1 (14, -1) -> (15.6, -2)
  line L2 (15.6, -2) -> (14, -3)
  line L3 (14, -3) -> (9, -5.3599)
  line L4 (9, -5.3599) -> (4, -7.6391)
  line L5 (4, -7.6391) -> (-1, -9.8369)
  line L6 (-1, -9.8369) -> (-6, -11.9525)
  line L7 (-6, -11.9525) -> (-11, -13.9852)
  line L8 (-11, -13.9852) -> (-16, -15.934)
  line L9 (-16, -15.934) -> (-21, -17.798)
  line L10 (-21, -17.798) -> (-26, -19.5764)
  line L11 (-26, -19.5764) -> (-31, -21.268)
  line L12 (-31, -21.268) -> (-36, -22.8717)
  line L13 (-36, -22.8717) -> (-41, -24.3863)
  line L14 (-41, -24.3863) -> (-46, -25.8104)
  line L15 (-46, -25.8104) -> (-51, -27.1426)
  line L16 (-51, -27.1426) -> (-56, -28.3813)
  line L17 (-56, -28.3813) -> (-61, -29.5247)
  line L18 (-61, -29.5247) -> (-66, -30.5707)
  line L19 (-66, -30.5707) -> (-71, -31.5171)
  line L20 (-71, -31.5171) -> (-76, -32.361)
  line L21 (-76, -32.361) -> (-81, -33.0993)
  line L22 (-81, -33.0993) -> (-86, -33.728)
  line L23 (-86, -33.728) -> (-91, -34.2421)
  line L24 (-91, -34.2421) -> (-96, -34.6347)
  line L25 (-96, -34.6347) -> (-101, -34.8951)
  line L26 (-101, -34.8951) -> (-106, -35)
  line L27 (-106, -35) -> (-120, -35)
  line L28 (-120, -35) -> (-120, -1)
extrude "finger (1)" add sketch "finger" along normal blind 20 separate body makes body 11 in component "Gripper finger R (TPU)"
ref_plane "WorkPlane2" through (0, 38.2, 0) normal (0, 1, 0) x (0, 0, 1) in component "Gripper finger R (TPU)"
sketch "rib pocket" plane through (0, 38.2, 0) normal (0, 1, 0) x (1, 0, 0) in component "Gripper finger R (TPU)"
  line L0 (-99.25, -2.8) -> (-90.75, -2.8)
  line L1 (-90.75, -2.8) -> (-94.75, -32.7485)
  line L2 (-94.75, -32.7485) -> (-99, -33.0078)
  line L3 (-99, -33.0078) -> (-103.25, -33.1642)
  line L4 (-103.25, -33.1642) -> (-99.25, -2.8)
extrude "rib pocket (1)" cut sketch "rib pocket" along normal blind 22 bodies 11 in component "Gripper finger R (TPU)"
sketch "rib pocket (1)" plane through (0, 38.2, 0) normal (0, 1, 0) x (1, 0, 0) in component "Gripper finger R (TPU)"
  line L0 (-89.25, -2.8) -> (-80.75, -2.8)
  line L1 (-80.75, -2.8) -> (-84.75, -31.7814)
  line L2 (-84.75, -31.7814) -> (-89, -32.2506)
  line L3 (-89, -32.2506) -> (-93.25, -32.6344)
  line L4 (-93.25, -32.6344) -> (-89.25, -2.8)
extrude "rib pocket (2)" cut sketch "rib pocket (1)" along normal blind 22 bodies 11 in component "Gripper finger R (TPU)"
sketch "rib pocket (2)" plane through (0, 38.2, 0) normal (0, 1, 0) x (1, 0, 0) in component "Gripper finger R (TPU)"
  line L0 (-79.25, -2.8) -> (-70.75, -2.8)
  line L1 (-70.75, -2.8) -> (-74.75, -30.3598)
  line L2 (-74.75, -30.3598) -> (-79, -31.0169)
  line L3 (-79, -31.0169) -> (-83.25, -31.5961)
  line L4 (-83.25, -31.5961) -> (-79.25, -2.8)
extrude "rib pocket (3)" cut sketch "rib pocket (2)" along normal blind 22 bodies 11 in component "Gripper finger R (TPU)"
sketch "rib pocket (3)" plane through (0, 38.2, 0) normal (0, 1, 0) x (1, 0, 0) in component "Gripper finger R (TPU)"
  line L0 (-69.25, -2.8) -> (-60.75, -2.8)
  line L1 (-60.75, -2.8) -> (-64.75, -28.5185)
  line L2 (-64.75, -28.5185) -> (-69, -29.3507)
  line L3 (-69, -29.3507) -> (-73.25, -30.1097)
  line L4 (-73.25, -30.1097) -> (-69.25, -2.8)
extrude "rib pocket (4)" cut sketch "rib pocket (3)" along normal blind 22 bodies 11 in component "Gripper finger R (TPU)"
sketch "rib pocket (4)" plane through (0, 38.2, 0) normal (0, 1, 0) x (1, 0, 0) in component "Gripper finger R (TPU)"
  line L0 (-59.25, -2.8) -> (-50.75, -2.8)
  line L1 (-50.75, -2.8) -> (-54.75, -26.2805)
  line L2 (-54.75, -26.2805) -> (-59, -27.2789)
  line L3 (-59, -27.2789) -> (-63.25, -28.2076)
  line L4 (-63.25, -28.2076) -> (-59.25, -2.8)
extrude "rib pocket (5)" cut sketch "rib pocket (4)" along normal blind 22 bodies 11 in component "Gripper finger R (TPU)"
sketch "rib pocket (5)" plane through (0, 38.2, 0) normal (0, 1, 0) x (1, 0, 0) in component "Gripper finger R (TPU)"
  line L0 (-49.25, -2.8) -> (-40.75, -2.8)
  line L1 (-40.75, -2.8) -> (-44.75, -23.6629)
  line L2 (-44.75, -23.6629) -> (-49, -24.8209)
  line L3 (-49, -24.8209) -> (-53.25, -25.9117)
  line L4 (-53.25, -25.9117) -> (-49.25, -2.8)
extrude "rib pocket (6)" cut sketch "rib pocket (5)" along normal blind 22 bodies 11 in component "Gripper finger R (TPU)"
sketch "rib pocket (6)" plane through (0, 38.2, 0) normal (0, 1, 0) x (1, 0, 0) in component "Gripper finger R (TPU)"
  line L0 (-39.25, -2.8) -> (-30.75, -2.8)
  line L1 (-30.75, -2.8) -> (-34.75, -20.6791)
  line L2 (-34.75, -20.6791) -> (-39, -21.9912)
  line L3 (-39, -21.9912) -> (-43.25, -23.2384)
  line L4 (-43.25, -23.2384) -> (-39.25, -2.8)
extrude "rib pocket (7)" cut sketch "rib pocket (6)" along normal blind 22 bodies 11 in component "Gripper finger R (TPU)"
sketch "rib pocket (7)" plane through (0, 38.2, 0) normal (0, 1, 0) x (1, 0, 0) in component "Gripper finger R (TPU)"
  line L0 (-29.25, -2.8) -> (-20.75, -2.8)
  line L1 (-20.75, -2.8) -> (-24.75, -17.3399)
  line L2 (-24.75, -17.3399) -> (-29, -18.8018)
  line L3 (-29, -18.8018) -> (-33.25, -20.2006)
  line L4 (-33.25, -20.2006) -> (-29.25, -2.8)
extrude "rib pocket (8)" cut sketch "rib pocket (7)" along normal blind 22 bodies 11 in component "Gripper finger R (TPU)"
sketch "rib pocket (8)" plane through (0, 38.2, 0) normal (0, 1, 0) x (1, 0, 0) in component "Gripper finger R (TPU)"
  line L0 (-19.25, -2.8) -> (-10.75, -2.8)
  line L1 (-10.75, -2.8) -> (-14.75, -13.6547)
  line L2 (-14.75, -13.6547) -> (-19, -15.2626)
  line L3 (-19, -15.2626) -> (-23.25, -16.809)
  line L4 (-23.25, -16.809) -> (-19.25, -2.8)
extrude "rib pocket (9)" cut sketch "rib pocket (8)" along normal blind 22 bodies 11 in component "Gripper finger R (TPU)"
sketch "rib pocket (9)" plane through (0, 38.2, 0) normal (0, 1, 0) x (1, 0, 0) in component "Gripper finger R (TPU)"
  line L0 (-9.25, -2.8) -> (-0.75, -2.8)
  line L1 (-0.75, -2.8) -> (-4.75, -9.6313)
  line L2 (-4.75, -9.6313) -> (-9, -11.3821)
  line L3 (-9, -11.3821) -> (-13.25, -13.0725)
  line L4 (-13.25, -13.0725) -> (-9.25, -2.8)
extrude "rib pocket (10)" cut sketch "rib pocket (9)" along normal blind 22 bodies 11 in component "Gripper finger R (TPU)"
sketch "tongue slot" plane through (0, 39.2, 0) normal (0, 1, 0) x (1, 0, 0) in component "Gripper finger R (TPU)"
  line L0 (-121, -5.3) -> (-107.8, -5.3)
  line L1 (-107.8, -5.3) -> (-107.8, -13.7)
  line L2 (-107.8, -13.7) -> (-121, -13.7)
  line L3 (-121, -13.7) -> (-121, -5.3)
extrude "tongue slot (1)" cut sketch "tongue slot" along normal blind 6.4 bodies 11 in component "Gripper finger R (TPU)"
ref_plane "WorkPlane3" through (0, 44.9, 0) normal (0, 1, 0) x (0, 0, 1) in component "Gripper finger R (TPU)"
sketch "screw hole (6)" plane through (0, 44.9, 0) normal (0, 1, 0) x (1, 0, 0) in component "Gripper finger R (TPU)"
  circle A0 centre (-114, -9.5) radius 1.7
extrude "screw hole (1)'" cut sketch "screw hole (6)" along normal blind 15.3 bodies 11 in component "Gripper finger R (TPU)"
ref_plane "WorkPlane1" through (0, 39.2, 0) normal (0, 1, 0) x (0, 0, 1) in component "Gripper finger L (TPU)"
sketch "finger (2)" plane through (0, 39.2, 0) normal (0, 1, 0) x (1, 0, 0) in component "Gripper finger L (TPU)"
  line L0 (-120, 1) -> (14, 1)
  line L1 (14, 1) -> (15.6, 2)
  line L2 (15.6, 2) -> (14, 3)
  line L3 (14, 3) -> (9, 5.3599)
  line L4 (9, 5.3599) -> (4, 7.6391)
  line L5 (4, 7.6391) -> (-1, 9.8369)
  line L6 (-1, 9.8369) -> (-6, 11.9525)
  line L7 (-6, 11.9525) -> (-11, 13.9852)
  line L8 (-11, 13.9852) -> (-16, 15.934)
  line L9 (-16, 15.934) -> (-21, 17.798)
  line L10 (-21, 17.798) -> (-26, 19.5764)
  line L11 (-26, 19.5764) -> (-31, 21.268)
  line L12 (-31, 21.268) -> (-36, 22.8717)
  line L13 (-36, 22.8717) -> (-41, 24.3863)
  line L14 (-41, 24.3863) -> (-46, 25.8104)
  line L15 (-46, 25.8104) -> (-51, 27.1426)
  line L16 (-51, 27.1426) -> (-56, 28.3813)
  line L17 (-56, 28.3813) -> (-61, 29.5247)
  line L18 (-61, 29.5247) -> (-66, 30.5707)
  line L19 (-66, 30.5707) -> (-71, 31.5171)
  line L20 (-71, 31.5171) -> (-76, 32.361)
  line L21 (-76, 32.361) -> (-81, 33.0993)
  line L22 (-81, 33.0993) -> (-86, 33.728)
  line L23 (-86, 33.728) -> (-91, 34.2421)
  line L24 (-91, 34.2421) -> (-96, 34.6347)
  line L25 (-96, 34.6347) -> (-101, 34.8951)
  line L26 (-101, 34.8951) -> (-106, 35)
  line L27 (-106, 35) -> (-120, 35)
  line L28 (-120, 35) -> (-120, 1)
extrude "finger (1)'" add sketch "finger (2)" along normal blind 20 separate body makes body 12 in component "Gripper finger L (TPU)"
ref_plane "WorkPlane2" through (0, 38.2, 0) normal (0, 1, 0) x (0, 0, 1) in component "Gripper finger L (TPU)"
sketch "rib pocket (10)" plane through (0, 38.2, 0) normal (0, 1, 0) x (1, 0, 0) in component "Gripper finger L (TPU)"
  line L0 (-99.25, 2.8) -> (-90.75, 2.8)
  line L1 (-90.75, 2.8) -> (-94.75, 32.7485)
  line L2 (-94.75, 32.7485) -> (-99, 33.0078)
  line L3 (-99, 33.0078) -> (-103.25, 33.1642)
  line L4 (-103.25, 33.1642) -> (-99.25, 2.8)
extrude "rib pocket (1)'" cut sketch "rib pocket (10)" along normal blind 22 bodies 12 in component "Gripper finger L (TPU)"
sketch "rib pocket (1) (2)" plane through (0, 38.2, 0) normal (0, 1, 0) x (1, 0, 0) in component "Gripper finger L (TPU)"
  line L0 (-89.25, 2.8) -> (-80.75, 2.8)
  line L1 (-80.75, 2.8) -> (-84.75, 31.7814)
  line L2 (-84.75, 31.7814) -> (-89, 32.2506)
  line L3 (-89, 32.2506) -> (-93.25, 32.6344)
  line L4 (-93.25, 32.6344) -> (-89.25, 2.8)
extrude "rib pocket (2)'" cut sketch "rib pocket (1) (2)" along normal blind 22 bodies 12 in component "Gripper finger L (TPU)"
sketch "rib pocket (2) (2)" plane through (0, 38.2, 0) normal (0, 1, 0) x (1, 0, 0) in component "Gripper finger L (TPU)"
  line L0 (-79.25, 2.8) -> (-70.75, 2.8)
  line L1 (-70.75, 2.8) -> (-74.75, 30.3598)
  line L2 (-74.75, 30.3598) -> (-79, 31.0169)
  line L3 (-79, 31.0169) -> (-83.25, 31.5961)
  line L4 (-83.25, 31.5961) -> (-79.25, 2.8)
extrude "rib pocket (3)'" cut sketch "rib pocket (2) (2)" along normal blind 22 bodies 12 in component "Gripper finger L (TPU)"
sketch "rib pocket (3) (2)" plane through (0, 38.2, 0) normal (0, 1, 0) x (1, 0, 0) in component "Gripper finger L (TPU)"
  line L0 (-69.25, 2.8) -> (-60.75, 2.8)
  line L1 (-60.75, 2.8) -> (-64.75, 28.5185)
  line L2 (-64.75, 28.5185) -> (-69, 29.3507)
  line L3 (-69, 29.3507) -> (-73.25, 30.1097)
  line L4 (-73.25, 30.1097) -> (-69.25, 2.8)
extrude "rib pocket (4)'" cut sketch "rib pocket (3) (2)" along normal blind 22 bodies 12 in component "Gripper finger L (TPU)"
sketch "rib pocket (4) (2)" plane through (0, 38.2, 0) normal (0, 1, 0) x (1, 0, 0) in component "Gripper finger L (TPU)"
  line L0 (-59.25, 2.8) -> (-50.75, 2.8)
  line L1 (-50.75, 2.8) -> (-54.75, 26.2805)
  line L2 (-54.75, 26.2805) -> (-59, 27.2789)
  line L3 (-59, 27.2789) -> (-63.25, 28.2076)
  line L4 (-63.25, 28.2076) -> (-59.25, 2.8)
extrude "rib pocket (5)'" cut sketch "rib pocket (4) (2)" along normal blind 22 bodies 12 in component "Gripper finger L (TPU)"
sketch "rib pocket (5) (2)" plane through (0, 38.2, 0) normal (0, 1, 0) x (1, 0, 0) in component "Gripper finger L (TPU)"
  line L0 (-49.25, 2.8) -> (-40.75, 2.8)
  line L1 (-40.75, 2.8) -> (-44.75, 23.6629)
  line L2 (-44.75, 23.6629) -> (-49, 24.8209)
  line L3 (-49, 24.8209) -> (-53.25, 25.9117)
  line L4 (-53.25, 25.9117) -> (-49.25, 2.8)
extrude "rib pocket (6)'" cut sketch "rib pocket (5) (2)" along normal blind 22 bodies 12 in component "Gripper finger L (TPU)"
sketch "rib pocket (6) (2)" plane through (0, 38.2, 0) normal (0, 1, 0) x (1, 0, 0) in component "Gripper finger L (TPU)"
  line L0 (-39.25, 2.8) -> (-30.75, 2.8)
  line L1 (-30.75, 2.8) -> (-34.75, 20.6791)
  line L2 (-34.75, 20.6791) -> (-39, 21.9912)
  line L3 (-39, 21.9912) -> (-43.25, 23.2384)
  line L4 (-43.25, 23.2384) -> (-39.25, 2.8)
extrude "rib pocket (7)'" cut sketch "rib pocket (6) (2)" along normal blind 22 bodies 12 in component "Gripper finger L (TPU)"
sketch "rib pocket (7) (2)" plane through (0, 38.2, 0) normal (0, 1, 0) x (1, 0, 0) in component "Gripper finger L (TPU)"
  line L0 (-29.25, 2.8) -> (-20.75, 2.8)
  line L1 (-20.75, 2.8) -> (-24.75, 17.3399)
  line L2 (-24.75, 17.3399) -> (-29, 18.8018)
  line L3 (-29, 18.8018) -> (-33.25, 20.2006)
  line L4 (-33.25, 20.2006) -> (-29.25, 2.8)
extrude "rib pocket (8)'" cut sketch "rib pocket (7) (2)" along normal blind 22 bodies 12 in component "Gripper finger L (TPU)"
sketch "rib pocket (8) (2)" plane through (0, 38.2, 0) normal (0, 1, 0) x (1, 0, 0) in component "Gripper finger L (TPU)"
  line L0 (-19.25, 2.8) -> (-10.75, 2.8)
  line L1 (-10.75, 2.8) -> (-14.75, 13.6547)
  line L2 (-14.75, 13.6547) -> (-19, 15.2626)
  line L3 (-19, 15.2626) -> (-23.25, 16.809)
  line L4 (-23.25, 16.809) -> (-19.25, 2.8)
extrude "rib pocket (9)'" cut sketch "rib pocket (8) (2)" along normal blind 22 bodies 12 in component "Gripper finger L (TPU)"